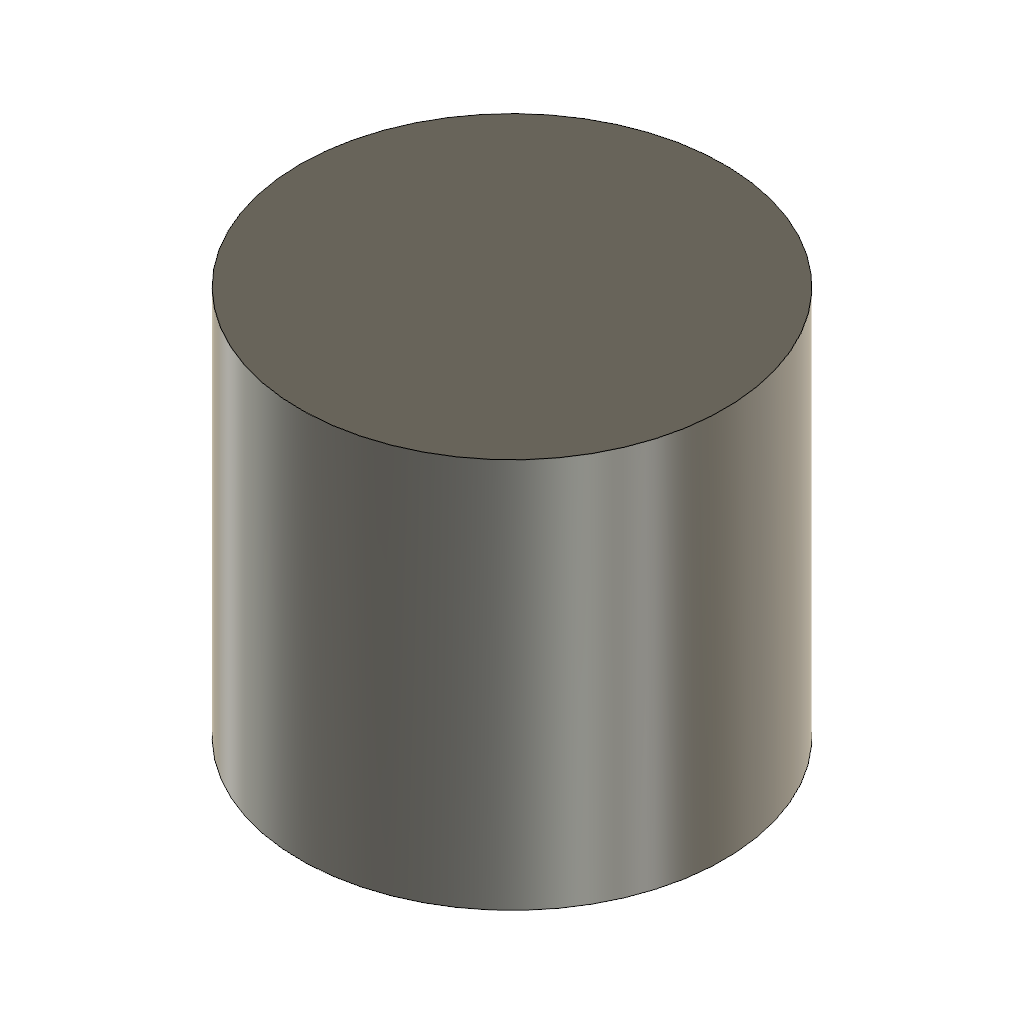
vendor_independent_extrusion23mm (Autodesk Fusion 360 design; units mm, degrees)
Autodesk Fusion 360 part; units mm, degrees
sketch "Authored Circle" plane through (0, 0, 0) normal (0, 0, 1) x (1, 0, 0)
  circle A0 centre (0, 0) radius 12.5
extrude "Authored Extrusion" add sketch "Authored Circle" along normal blind 23
equation "authoredLength = 23 mm" comment "Independently authored semantic parameter"
equation "d2 = authoredLength"
